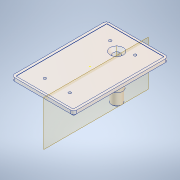
# Autodesk Inventor part: 1.1_3_Shaft_A
Saved by Autodesk Inventor 2021 (Build 250183000, 183)
## iProperties
Created: 2025-11-13
Part Number: 1.1_3_Shaft_A
Material: Aluminum 6061
Document SubType Name: Modeling
Designer: Admin
Density: 2.7 g/cm^3
Appearance: Aluminum - Flat
Mass: 3801.95 g
Surface Area: 1678.07 cm^2
Volume: 1408.13 cm^3
Author: Admin
Autodesk Inventor part; units mm, degrees
ref_plane "XZ Plane" through (0, 0, 0) normal (0, 1, 0) x (-1, 0, 0)
ref_plane "XY Plane" through (0, 0, 0) normal (0, 0, 1) x (1, 0, 0)
sketch "Sketch2" plane through (0, 0, 0) normal (0, 1, 0) x (-1, 0, 0)
  line L0 (105, -160) -> (-105, -160)
  line L1 (-105, -160) -> (-105, 160)
  line L2 (-105, 160) -> (105, 160)
  line L3 (105, 160) -> (105, -160)
  line L4 (0, -224) -> (0, 224) projected
  line L5 (-147, 0) -> (147, 0) projected
  point P0 (0, 0)
  point P1 (0, -160)
  point P2 (-105, 0)
  dimension "d4" = 320
  dimension "d5" = 210
  constraints: 8 end point, 2 midpoint, 2 parallel, 2 point on line, 1 horizontal, 1 perpendicular
  measures "d4" distance of L0.end L1.end
  measures "d5" distance of L0.start L0.end
extrude "Extrusion1" add sketch "Sketch2" along normal blind 21
sketch "Sketch4" plane through (0, 21, 0) normal (0, 1, 0) x (1, 0, 0)
  line L0 (-96.5, -153) -> (96.5, -153)
  line L1 (96.5, -153) -> (96.5, 153)
  line L2 (96.5, 153) -> (-96.5, 153)
  line L3 (-96.5, 153) -> (-96.5, -153)
  line L4 (-96.5, -153) -> (96.5, 153) construction
  line L5 (96.5, -153) -> (-96.5, 153) construction
  point P0 (0, 0)
  dimension "d8" = 306
  dimension "d9" = 193
  constraints: 12 end point, 2 midpoint, 2 parallel, 1 horizontal, 1 perpendicular
  measures "d8" distance of L0.end L1.end
  measures "d9" distance of L1.end L2.end
extrude "Extrusion2" cut sketch "Sketch4" against normal blind 1
fillet "Fillet1" radius 2 4 edges at (-96.5, 20.5, -153) (-96.5, 20.5, 153) (96.5, 20.5, 153) (96.5, 20.5, -153)
sketch "Sketch5" plane through (0, 0, 0) normal (1, 0, 0) x (0, 1, 0)
  line L0 (0, 160) -> (0, -160) projected
  line L1 (0, -40) -> (-5, -40)
  line L2 (-5, -40) -> (-5, -59)
  line L3 (-5, -59) -> (-7, -59)
  line L4 (-7, -59) -> (-7, -65)
  line L5 (-7, -65) -> (-33, -65)
  line L6 (-33, -65) -> (-33, -67)
  line L7 (-148.4, 0) -> (71.4, 0) projected
  line L8 (0, -40) -> (0, -90)
  line L9 (-33, -67) -> (-56, -67)
  line L10 (-56, -67) -> (-56, -70)
  line L11 (-56, -70) -> (-87, -70)
  line L12 (-87, -70) -> (-87, -72.5)
  line L13 (-87, -72.5) -> (-129, -72.5)
  line L14 (-129, -72.5) -> (-129, -90)
  line L15 (0, -90) -> (-129, -90)
  line L16 (0, -160) -> (0, 160) projected
  line L17 (0, -160) -> (21, -160) projected
  point P0 (0, 0)
  dimension "d15" = 5
  dimension "d22" = 26
  dimension "d23" = 6
  dimension "d25" = 28
  dimension "d31" = 23
  dimension "d32" = 31
  dimension "d33" = 17.5
  dimension "d34" = 42
  dimension "d35" = 25
  dimension "d36" = 50
  dimension "d37" = 70
  dimension "d57" = 20
  dimension "d58" = 2
  constraints: 28 end point, 11 perpendicular, 1 collinear, 1 horizontal, 1 point on line
  measures "d15" distance between parallel lines of L0 L2
  measures "d22" distance of L4.end L5.end
  measures "d23" distance of L3.end L4.end
  measures "d25" distance between parallel lines of L6 L2
  measures "d31" distance of L6.end L9.end
  measures "d32" distance of L10.end L11.end
  measures "d33" distance between parallel lines of L15 L13
  measures "d34" distance of L12.end L13.end
  measures "d35" distance between parallel lines of L15 L5
  measures "d36" distance between parallel lines of L15 L1
  measures "d37" distance between parallel lines of L15 L17
  measures "d57" distance between parallel lines of L15 L11
  measures "d58" distance between parallel lines of L5 L9
revolve "Revolution2" add sketch "Sketch5" angle 360 about axis through (0, 0, -90) along (0, -1, 0)
fillet "Fillet2" radius 10 4 edges at (-105, 10.5, 160) (-105, 10.5, -160) (105, 10.5, -160) (105, 10.5, 160)
sketch "Sketch7" plane through (0, 20, 0) normal (0, 1, 0) x (1, 0, 0)
  line L0 (-42, -110) -> (42, -110)
  line L1 (42, -110) -> (42, 110)
  line L2 (42, 110) -> (-42, 110)
  line L3 (-42, 110) -> (-42, -110)
  line L4 (-42, -110) -> (42, 110) construction
  line L5 (42, -110) -> (-42, 110) construction
  line L6 (96.5, 151) -> (96.5, -151) projected
  line L7 (94.5, -153) -> (-94.5, -153) projected
  point P0 (0, 0)
  dimension "d39" = 43
  dimension "d47" = 84
  constraints: 12 end point, 2 midpoint, 2 parallel, 1 horizontal, 1 perpendicular
  measures "d39" distance between parallel lines of L7 L0
  measures "d47" distance of L0.start L0.end
hole "Hole1" at (-42, 20, 110) at (-42, 20, -110) at (42, 20, -110) at (42, 20, 110) direction (0, -1, 0) diameter 9 end through all clearance for "Countersunk Flat Head Screw ISO 2009/7046" size "M8" standard "ISO"
sketch "Sketch8" plane through (0, 0, 0) normal (0, -1, 0) x (1, 0, 0)
  line L0 (42, 110) -> (-42, 110) construction
  line L1 (-42, 110) -> (-42, -110) construction
  line L2 (-42, -110) -> (42, -110) construction
  line L3 (42, -110) -> (42, 110) construction
  circle A0 centre (-42, 110) radius 4.5 projected
  circle A1 centre (42, -110) radius 4.5 projected
  arc A2 (-43.7937, -114.1271) -> (-46.3346, -108.7911) centre (-42, -110) ccw projected
  circle A3 centre (42, 110) radius 4.5 projected
  line L4 (42, 102.4944) -> (35.5, 106.2472)
  line L5 (35.5, 106.2472) -> (35.5, 113.7528)
  line L6 (35.5, 113.7528) -> (42, 117.5056)
  line L7 (42, 117.5056) -> (48.5, 113.7528)
  line L8 (48.5, 113.7528) -> (48.5, 106.2472)
  line L9 (48.5, 106.2472) -> (42, 102.4944)
  line L10 (42, -102.4944) -> (48.5, -106.2472)
  line L11 (48.5, -106.2472) -> (48.5, -113.7528)
  line L12 (48.5, -113.7528) -> (42, -117.5056)
  line L13 (42, -117.5056) -> (35.5, -113.7528)
  line L14 (35.5, -113.7528) -> (35.5, -106.2472)
  line L15 (35.5, -106.2472) -> (42, -102.4944)
  line L16 (-42, 102.4944) -> (-48.5, 106.2472)
  line L17 (-48.5, 106.2472) -> (-48.5, 113.7528)
  line L18 (-48.5, 113.7528) -> (-42, 117.5056)
  line L19 (-42, 117.5056) -> (-35.5, 113.7528)
  line L20 (-35.5, 113.7528) -> (-35.5, 106.2472)
  line L21 (-35.5, 106.2472) -> (-42, 102.4944)
  line L22 (-42, -102.4944) -> (-35.5, -106.2472)
  line L23 (-35.5, -106.2472) -> (-35.5, -113.7528)
  line L24 (-35.5, -113.7528) -> (-42, -117.5056)
  line L25 (-42, -117.5056) -> (-48.5, -113.7528)
  line L26 (-48.5, -113.7528) -> (-48.5, -106.2472)
  line L27 (-48.5, -106.2472) -> (-42, -102.4944)
  circle A4 centre (-42, 110) radius 4.5
  circle A5 centre (42, 110) radius 4.5
  circle A6 centre (42, -110) radius 4.5
  circle A7 centre (-42, -110) radius 4.5
  point P0 (0, 0)
  point P1 (-38.6653, -113.0216)
  point P2 (-37.5, -110)
  dimension "d75" = 13
  constraints: 56 end point, 10 coincident, 4 centre point, 4 point on line, 3 equal length, 3 perpendicular, 2 concentric, 1 horizontal, 52 other
  measures "d75" distance between parallel lines of L5 L8
extrude "Extrusion3" cut sketch "Sketch8" against normal mid plane 17 contours A1 | A3 | L4 L5 L6 L7 L8 L9 | L10 L11 L12 L13 L14 L15 | L16 L17 L18 L19 L20 L21 | L22 L23 L24 L25 L26 L27
sketch "Sketch9" plane through (0, 20, 0) normal (0, 1, 0) x (1, 0, 0)
  point P0 (0, 0)
chamfer "Chamfer2" distance 10 angle 45 8 edges at (0, 0, -160) (-102.0711, 0, -157.0711) (-105, 0, 0) (-102.0711, 0, 157.0711) (0, 0, 160) (102.0711, 0, 157.0711) (105, 0, 0) (102.0711, 0, -157.0711)
sketch "Sketch10" plane through (0, 0, 0) normal (1, 0, 0) x (0, 1, 0)
  line L0 (21, 151) -> (21, -151) projected
  line L1 (21, -90) -> (21, -78)
  line L2 (-9, -78) -> (-9, -90)
  line L3 (-9, -90) -> (21, -90)
  line L4 (21, -78) -> (-9, -78)
  line L5 (10, 150) -> (10, -150) projected
  line L6 (51, -90) -> (-159, -90) projected
  point P0 (0, 0)
  dimension "d59" = 12
  dimension "d60" = 30
  constraints: 8 end point, 2 perpendicular, 2 point on line, 1 collinear, 1 vertical
  measures "d59" distance between parallel lines of L3 L4
  measures "d60" distance of L1.end L2.start
revolve "Revolution3" cut sketch "Sketch10" angle 360 about axis through (0, -71.5, -90) along (0, -1, 0)
chamfer "Chamfer3" distance 10 angle 45 1 edges at (0, 20, -102)
ref_plane "Work Plane1" through (20, -71.5, -90) normal (1, 0, 0) x (0, 1, 0)
sketch "Sketch11" plane through (20, -71.5, -90) normal (1, 0, 0) x (0, 1, 0)
  line L0 (-8, 0) -> (8, 0) construction
  line L1 (-8, -6) -> (8, -6)
  line L2 (8, 6) -> (-8, 6)
  arc A0 (-8, 6) -> (-8, -6) centre (-8, 0) ccw
  arc A1 (8, -6) -> (8, 6) centre (8, 0) ccw
  line L3 (-15.5, 20) -> (-15.5, -20) projected
  line L4 (122.5, 0) -> (-87.5, 0) projected
  point P0 (71.5, 90)
  point P1 (0, 0)
  dimension "d65" = 12
  dimension "d66" = 16
  dimension "d67" = 15.5
  constraints: 8 end point, 4 point on circle, 4 tangent, 2 centre point, 1 horizontal, 1 midpoint, 1 parallel, 1 point on line
  measures "d65" distance between parallel lines of L1 L2
  measures "d66" distance of L0.start L0.end
  measures "d67" distance from line of L3 point (0, 0)
extrude "Extrusion4" [suppressed]
fillet "Fillet3" radius 0.5 1 edges at (0, -7, -115)
fillet "Fillet4" radius 0.3 2 edges at (0, -56, -110) (0, -87, -107.5)
chamfer "Chamfer5" distance 2 angle 45 1 edges at (0, -5, -121)
chamfer "Chamfer7" distance 0.5 angle 45 20 edges at (-35.5, -5, -110) (-38.661, -5, -115.5778) (-44.7421, -5, -104.0776) (-38.75, -5, -104.3708) (-35.5, 0, 110) (-38.75, 0, 104.3708) (-45.25, 0, 104.3708) (-48.5, 0, 110) (-38.75, 0, 115.6292) (-45.25, 0, 115.6292) (38.75, 0, 104.3708) (45.25, 0, 104.3708) (48.5, 0, 110) (35.5, 0, 110) (45.25, 0, 115.6292) (38.75, 0, 115.6292) (38.661, -5, -115.5778) (44.7421, -5, -104.0776) (38.75, -5, -104.3708) (35.5, -5, -110)
sketch "Sketch12" plane through (0, -129, -90) normal (0, -1, 0) x (1, 0, 0)
  line L0 (-7, 7) -> (7, 7) construction
  line L1 (7, 7) -> (7, -7) construction
  line L2 (7, -7) -> (-7, -7) construction
  line L3 (-7, -7) -> (-7, 7) construction
  line L4 (-7, 7) -> (7, -7) construction
  line L5 (7, 7) -> (-7, -7) construction
  point P0 (0, 90)
  point P1 (0, 0)
  point P2 (0, 0)
  point P3 (0, 0)
  dimension "d86" = 14
  constraints: 12 end point, 5 coincident, 3 midpoint, 2 parallel, 2 perpendicular, 1 horizontal
  measures "d86" distance of L0.end L1.end
hole "Hole2" at (7, -129, -83) at (7, -129, -97) at (-7, -129, -97) at (-7, -129, -83) direction (0, 1, 0) diameter 4.917 depth 30 tip angle 118 thread size "M6x1" class "6H" standard "ISO Metric profile"
chamfer "Chamfer8" distance 2 angle 45 1 edges at (0, -129, -107.5)
body "Solid2"
